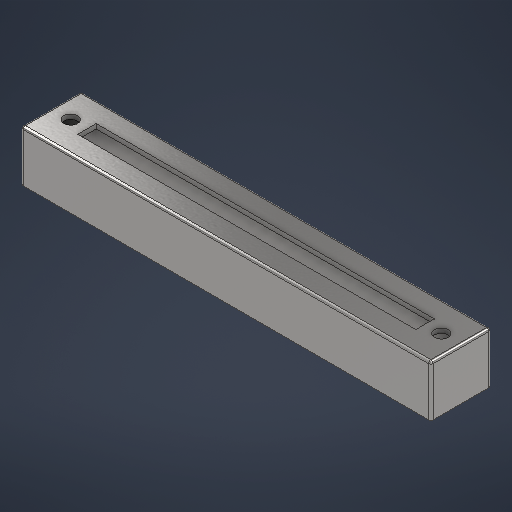
# Autodesk Inventor part: Potikan runko
Saved by Autodesk Inventor 2026.1 (Build 301233020, 233B)
## iProperties
Created: 2025-11-03
Part Number: Potikan runko
Material: Steel, Galvanized
Document SubType Name: Modeling
Designer: kuuse
Density: 7.85 g/cm^3
Appearance: Galvanized
Author: kuuse
Autodesk Inventor part; units mm, degrees
ref_plane "YZ Plane" through (0, 0, 0) normal (1, 0, 0) x (0, 1, 0)
ref_plane "XZ Plane" through (0, 0, 0) normal (0, 1, 0) x (-1, 0, 0)
ref_plane "XY Plane" through (0, 0, 0) normal (0, 0, 1) x (1, 0, 0)
sketch "Sketch1" plane through (0, 0, 0) normal (0, 1, 0) x (-1, 0, 0)
  line L0 (44.25, 6.5) -> (-44.25, 6.5)
  line L1 (-44.25, 6.5) -> (-44.25, -6.5)
  line L2 (-44.25, -6.5) -> (44.25, -6.5)
  line L3 (44.25, -6.5) -> (44.25, 6.5)
  line L4 (44.25, 6.5) -> (-44.25, -6.5) construction
  line L5 (-44.25, 6.5) -> (44.25, -6.5) construction
  line L6 (36.5, 2) -> (-36.5, 2)
  line L7 (-36.5, 2) -> (-36.5, -2)
  line L8 (-36.5, -2) -> (36.5, -2)
  line L9 (36.5, -2) -> (36.5, 2)
  line L10 (36.5, 2) -> (-36.5, -2) construction
  line L11 (-36.5, 2) -> (36.5, -2) construction
  line L12 (40, 0) -> (-40, 0) construction
  circle A0 centre (40, 0) radius 1.5
  circle A1 centre (-40, 0) radius 1.5
  line L13 (43.25, -5.5) -> (-43.25, -5.5)
  line L14 (-43.25, -5.5) -> (-43.25, 5.5)
  line L15 (-43.25, 5.5) -> (43.25, 5.5)
  line L16 (43.25, 5.5) -> (43.25, -5.5)
  point P0 (0, 0)
  dimension "d0" = 88.5
  dimension "d1" = 13
  dimension "d2" = 73
  dimension "d3" = 4
  dimension "d4" = 80
  dimension "d5" = 3
  dimension "d6" = 3
  dimension "d11" = 1
  constraints: 34 end point, 6 parallel, 5 midpoint, 3 horizontal, 3 perpendicular, 2 centre point, 2 coincident, 3 other
  measures "d0" distance of L2.end L1.end
  measures "d1" distance of L1.end L0.end
  measures "d2" distance of L8.end L7.end
  measures "d3" distance of L7.end L6.end
  measures "d4" distance of L12.start L12.end
  measures "d5" diameter of A0
  measures "d6" diameter of A1
  measures "d11" distance between parallel lines of L2 L13
extrude "Extrusion1" add sketch "Sketch1" along normal blind 11 contours L3 L2 L1 L0 | L13 L14 L15 L16
extrude "Extrusion2" add sketch "Sketch1" along normal blind 2 contours L9 L8 L7 L6 | A0 | A1
extrude "Extrusion3" cut sketch "Sketch1" along normal blind 8 from surface at 2 contours L13 L14 L15 L16
thread "Thread1" size "M3x0.5" class "6H" standard "ANSI Metric M Profile" length 20
thread "Thread2" size "M3x0.5" class "6H" standard "ANSI Metric M Profile" length 20
fillet "Fillet1" radius 0.5 8 edges at (-44.25, 5.5, 6.5) (0, 11, 6.5) (0, 11, -6.5) (-44.25, 5.5, -6.5) (-44.25, 11, 0) (44.25, 11, 0) (44.25, 5.5, 6.5) (44.25, 5.5, -6.5)
body "Solid1"
